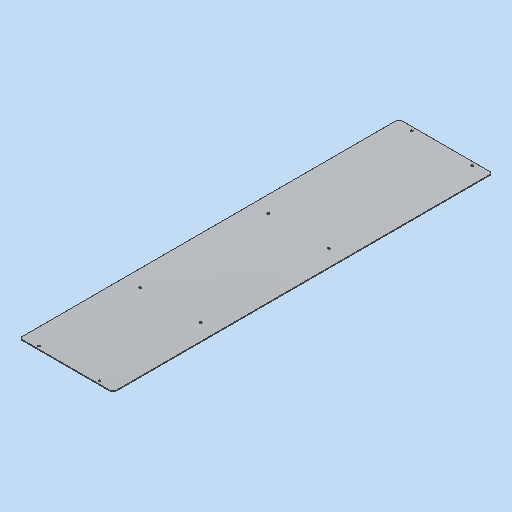
# Autodesk Inventor part: MM0948AN140_G01_125
Saved by Autodesk Inventor 2023.3 (Build 273359000, 359)
## iProperties
Created: 2024-01-04
Part Number: MM0948AN140_G01_125
Material: 3.3535 AlMg3 - AW 5754 (Blech)
Description: =<RBPARTNOTITLE2>
Document SubType Name: Sheet Metal
Designer: RIC7AN
Mass: 1345.25 g
Surface Area: 5037.18 cm^2
Volume: 498.424 cm^3
Density: 2.699 g/cm^3
Sheet Metal Rule: Standard_mm
Appearance: Aluminium AnP
RBPARTMADEOF: 2 x 1006 x 248 (FM)
RBDRAWINGMISSINGSPEC: --
AnP_Kategorie: 1
RBPARTNOTITLE2: Anfertigungsteil
RBSURFACE: anodised E6/EV1 colourless
RBPARTNOTITLE1: manufactured part
RBSURFACE2: eloxiert E6/EV1 aluminiumfarbig
AnP_Material: =<Material>
RBMATERIAL: =<Material>
RBMATNO: =<Part Number>
RBPARTNO: SIEHE MNR
MaxAbmaße: 2 x 1006 x 248 (FM)
Author: RIC7AN
Keywords: =<RBPARTMADEOF>
Comments: =<RBSURFACE2>
Revision Number: 01
Autodesk Inventor part; units mm, degrees
ref_plane "YZ Plane" through (0, 0, 0) normal (1, 0, 0) x (0, 1, 0)
ref_plane "XZ Plane" through (0, 0, 0) normal (0, 1, 0) x (-1, 0, 0)
ref_plane "XY Plane" through (0, 0, 0) normal (0, 0, 1) x (1, 0, 0)
sketch "Skizze1" plane through (0, 0, 0) normal (0, 0, 1) x (1, 0, 0)
  line L0 (-124, 1006) -> (124, 1006)
  line L1 (124, 1006) -> (124, 0)
  line L2 (124, 0) -> (-124, 0)
  line L3 (-124, 0) -> (-124, 1006)
  line L4 (0, 1207.2) -> (0, -201.2)
  line L5 (-173.6, 0) -> (173.6, 0)
  point P0 (0, 0)
  dimension "d0" = 248
  dimension "d1" = 1006
  measures "d0" distance of L0.start L0.end
  measures "d1" distance of L0.end L1.end
extrude "Grobblech1" add sketch "Skizze1" along normal blind 2
sketch "Skizze2" plane through (0, 0, 2) normal (0, 0, 1) x (1, 0, 0)
  line L0 (-124, 1006) -> (124, 1006) projected
  line L1 (-124, 0) -> (-124, 1006) projected
  line L2 (0, 1207.2) -> (0, -201.2) projected
  point P0 (0, 0)
  point P1 (-80, 996)
  point P2 (80, 996)
  point P3 (-80, 616)
  point P4 (80, 616)
  point P5 (-80, 8)
  point P6 (80, 8)
  point P7 (-80, 276)
  point P8 (80, 276)
  dimension "d3" = 10
  dimension "d4" = 380
  dimension "d5" = 340
  dimension "d6" = 268
  dimension "d8" = 160
  constraints: 6 vertical alignment, 4 horizontal alignment, 1 symmetric about line
  measures "d3" distance from line of L0 point (80, 996)
  measures "d4" distance of point (80, 616) point (80, 996)
  measures "d5" distance of point (80, 276) point (80, 616)
  measures "d6" distance of point (80, 8) point (80, 276)
  measures "d8" distance of point (80, 996) point (-80, 996)
hole "Bohrung1" at (-80, 996, 2) at (80, 996, 2) at (-80, 616, 2) at (80, 616, 2) at (-80, 8, 2) at (80, 8, 2) at (-80, 276, 2) at (80, 276, 2) direction (0, 0, -1) diameter 6 end through all
chamfer "Eckenfase1" distance 5 angle 45 4 edges at (-124, 0, 1) (124, 0, 1) (124, 1006, 1) (-124, 1006, 1)
equation "\"d14\" = Stärke"
equation "\"d2\" = Stärke"
equation "\"Biegeradius\" = Stärke"
equation "\"BreiteBiegungsfreistellung\" = Stärke"
equation "\"TiefeBiegungsfreistellung\" = 0.5 * Stärke"
equation "\"GrößeEckenfreistellung\" = 4 * Stärke"
equation "\"MinimalRest\" = 2 * Stärke"
equation "\"Übergangsradius\" = Biegeradius"
equation "\"JacobiRadiusGröße\" = Biegeradius"
equation "\"Abstandsgröße\" = Stärke"
equation "\"Stärke\" = 2"
